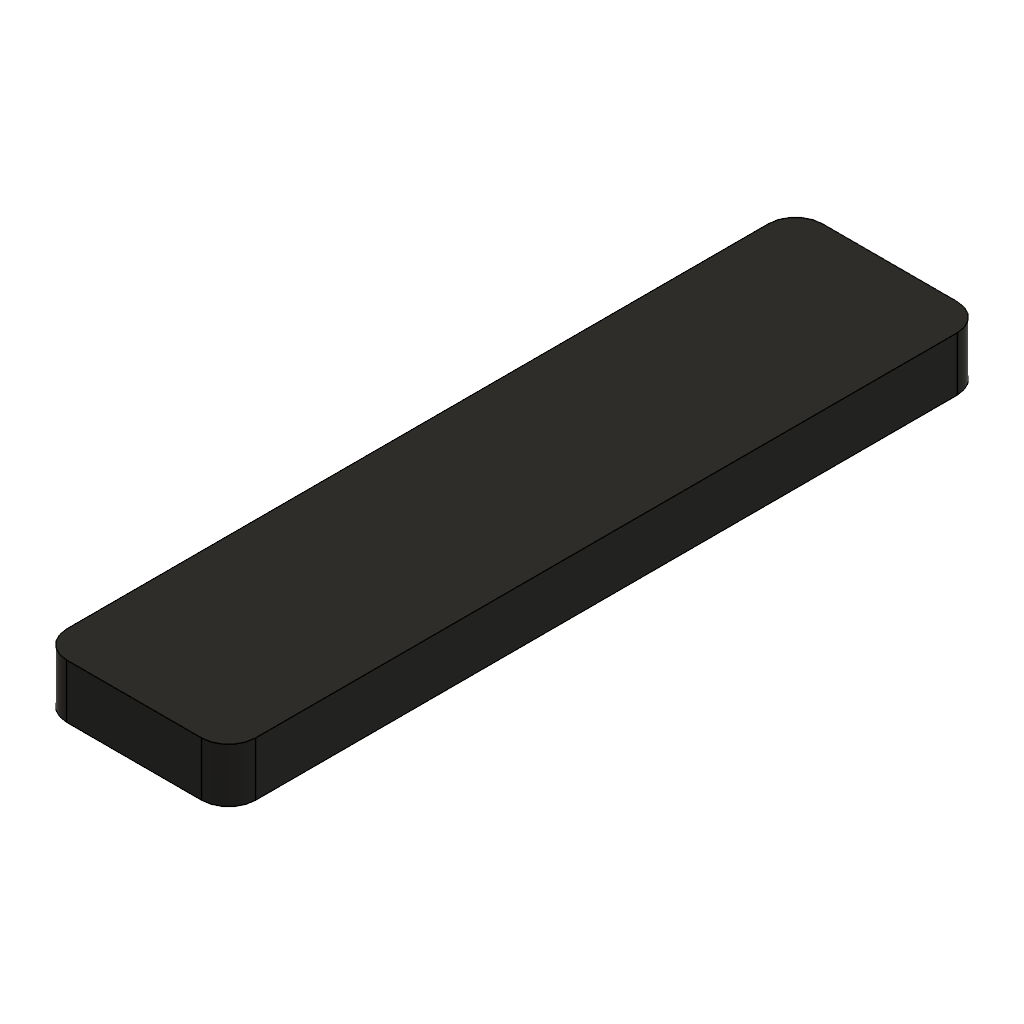
LTE_Antenna (Autodesk Fusion 360 design; units mm, degrees)
part number: 2026-10-22-00-28-00-261
Autodesk Fusion 360 part; units mm, degrees
sketch "Sketch1" plane through (0, 0, 0) normal (0, 1, 0) x (1, 0, 0)
  line L0 (3.5, -14) -> (-3.5, -14)
  line L1 (-3.5, -14) -> (-3.5, 14)
  line L2 (-3.5, 14) -> (3.5, 14)
  line L3 (3.5, 14) -> (3.5, -14)
  line L4 (3.5, -14) -> (-3.5, 14) construction
  line L5 (-3.5, -14) -> (3.5, 14) construction
  dimension "d1" = 7
  dimension "d2" = 28
  constraint horizontal L0
  constraint perpendicular L0 L1
  constraint parallel L0 L2
  constraint parallel L1 L3
  constraint coincident L4 origin
  constraint coincident L5 origin
  measures "d1" distance of L1.end L2.end
  measures "d2" distance of L0.end L1.end
extrude "Extrude1" add sketch "Sketch1" along normal blind 2
fillet "Fillet1" radius 1 1 edges at (3.5, 1, 14)
fillet "Fillet2" radius 1 1 edges at (3.5, 1, -14)
fillet "Fillet3" radius 1 1 edges at (-3.5, 1, 14)
fillet "Fillet4" radius 1 1 edges at (-3.5, 1, -14)
